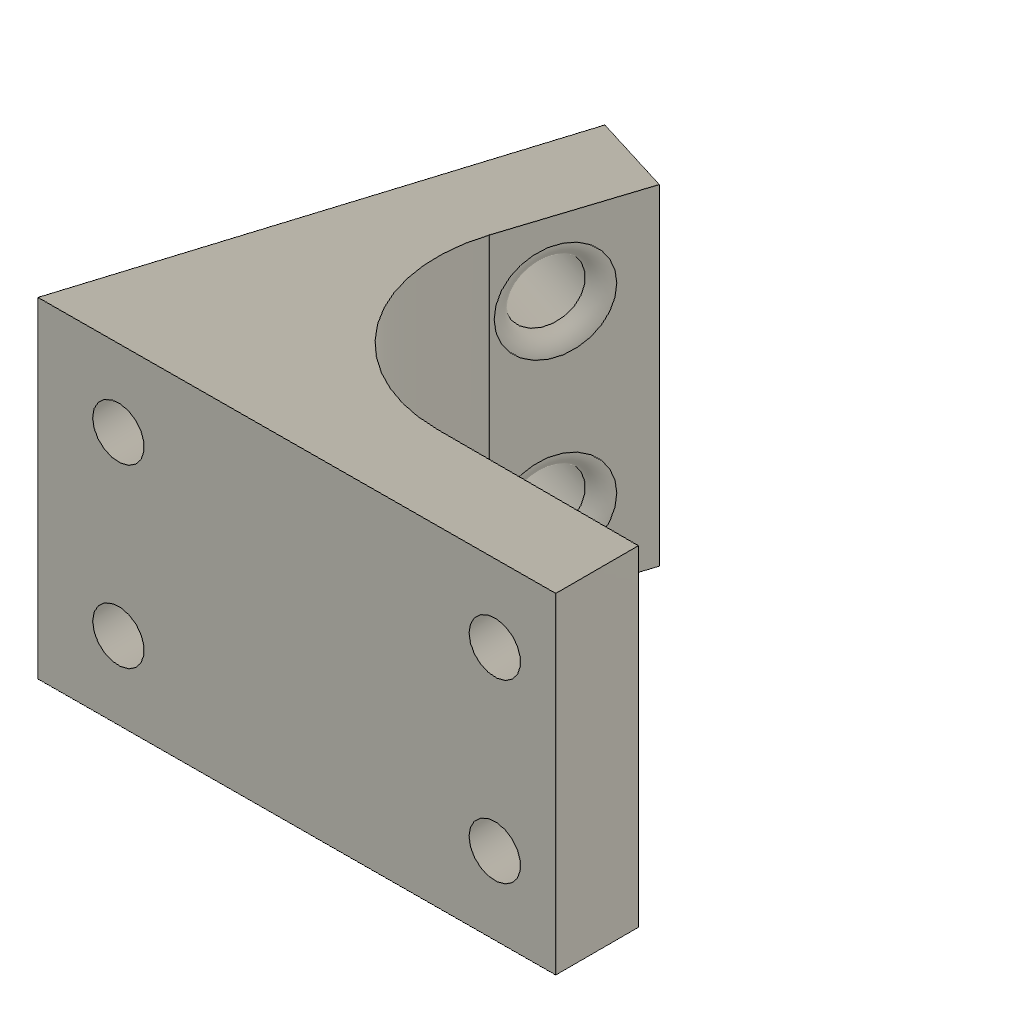
soporte_final_de_carrera_izquierdo (Autodesk Fusion 360 design; units mm, degrees)
Autodesk Fusion 360 part; units mm, degrees
sketch "Boceto1" plane through (0, 0, 0) normal (0, 1, 0) x (1, 0, 0)
sketch "Boceto2" plane through (0, 0, 0) normal (0, 1, 0) x (1, 0, 0)
  line L0 (-2.4765, -16.3875) -> (28.7043, -16.2321)
  line L1 (-0.8695, -11.2008) -> (-2.4765, -16.3875)
  line L2 (28.7038, -11.2321) -> (-0.8695, -11.2008)
  line L3 (28.7043, -16.2321) -> (28.7038, -11.2321)
  line L4 (0.003, -0.5995) -> (0.0504, -0.0236)
  line L5 (5.8748, 9.7875) -> (5.6392, 9.8069)
  line L6 (-2.0966, -0.0236) -> (7.9894, -0.0236) construction
  line L7 (-0.8695, -11.2008) -> (0.0412, -8.2614)
  line L8 (0.0412, -8.2614) -> (3.4344, 2.6907)
  line L9 (3.4344, 2.6907) -> (5.6392, 9.8069)
  line L10 (5.6392, 9.8069) -> (10.4153, 8.3271)
  line L11 (10.4153, 8.3271) -> (4.1469, -11.2061)
  line L12 (5.8705, 9.7352) -> (5.8748, 9.7875)
  line L13 (0, 0) -> (0.003, -0.5995) construction
  line L14 (0.0412, -8.2614) -> (0.0922, -18.4956) construction
  point P0 (3.4743, -16.237)
  point P1 (-1.1967, -15.176)
  point P2 (-1.5762, -19.7876)
  dimension "d1" = 5
  dimension "d3" = 5.1866
  dimension "d4" = 17.5
  dimension "d27" = 3.0772
  dimension "d28" = 5
  constraint coincident L11.end L2
  constraint coincident L13.start origin
  constraint perpendicular L0 L14
  constraint perpendicular L4 L5
  constraint parallel L1 L7
  constraint parallel L7 L8
  constraint parallel L8 L9
  constraint perpendicular L9 L10
  constraint coincident L10 L12.start
  constraint collinear L13 L14
  measures "d1" distance of L2.start L0.end
  measures "d3" vertical distance of L1.start L0.start
  measures "d4" angle of L1 L14
  measures "d27" distance of L1.start L7.end
  measures "d28" distance of L5.end L10.end
extrude "Extruir1" add sketch "Boceto2" along normal blind 20 contours L0 L1 L2 L3 | L2 L7 L8 L9 L10 L11
sketch "Boceto4" plane through (0.0816, 0, 16.3747) normal (0.004984, 0, 0.999988) x (0.999988, 0, -0.004984)
  line L0 (-2.5581, 0) -> (28.6231, 0)
  line L1 (28.6231, 0) -> (28.6231, 20)
  line L2 (28.6231, 20) -> (-2.5581, 20)
  line L3 (-2.5581, 20) -> (-2.5581, 0)
  line L4 (-0.378, 2.01) -> (27.622, 2.01)
  line L5 (27.622, 2.01) -> (27.622, 18.01)
  line L6 (27.622, 18.01) -> (-0.378, 18.01)
  line L7 (-0.378, 18.01) -> (-0.378, 2.01)
  line L8 (-0.378, 2.01) -> (27.622, 18.01) construction
  line L9 (27.622, 2.01) -> (-0.378, 18.01) construction
  circle A0 centre (2.292, 15.34) radius 1.55
  line L10 (13.622, 8.2976) -> (13.622, 12.2565) construction
  line L11 (11.7827, 10.01) -> (15.7906, 10.01) construction
  circle A1 centre (24.952, 15.34) radius 1.55
  circle A2 centre (24.952, 4.68) radius 1.55
  circle A3 centre (2.292, 4.68) radius 1.55
  point P0 (13.622, 10.01)
  dimension "d17" = 28
  dimension "d18" = 16
  dimension "d19" = 3.1
  dimension "d20" = 2.67
  dimension "d21" = 2.67
  constraint horizontal L4
  constraint perpendicular L4 L5
  constraint parallel L4 L6
  constraint parallel L5 L7
  constraint coincident L8 P0
  constraint coincident L9 P0
  constraint perpendicular L2 L10
  constraint perpendicular L10 L11
  constraint symmetric A0 L10 A1
  constraint symmetric A0 L11 A3
  constraint symmetric L11 A1 A2
  measures "d17" distance of L5.end L6.end
  measures "d18" distance of L4.end L5.end
  measures "d19" diameter of A0
  measures "d20" distance of L6 A0.centre
  measures "d21" distance of L7 A0.centre
extrude "Extruir3" cut sketch "Boceto4" against normal blind 6 contours A0 | A1 | A2 | A3
sketch "Boceto5" plane through (7.0201, 0, 2.2528) normal (0.952174, 0, 0.305557) x (0.305557, 0, -0.952174)
  line L0 (-9.4031, 0) -> (11.1113, 0)
  line L1 (11.1113, 0) -> (11.1113, 20)
  line L2 (11.1113, 20) -> (-9.4031, 20)
  line L3 (-9.4031, 20) -> (-9.4031, 0)
  circle A0 centre (6.1113, 4.5) radius 1.95
  circle A1 centre (6.1113, 15.5) radius 1.95
  dimension "d29" = 3.9
  dimension "d30" = 4.5
  dimension "d31" = 3.9
  dimension "d32" = 4.5
  dimension "d33" = 5
  dimension "d34" = 5
  measures "d29" diameter of A0
  measures "d30" distance of L0 A0.centre
  measures "d31" diameter of A1
  measures "d32" distance of L2 A1.centre
  measures "d33" distance of L1 A0.centre
  measures "d34" distance of L1 A1.centre
extrude "Extruir4" cut sketch "Boceto5" against normal blind 7 contours A0 | A1
fillet "Empalme3" radius 1 2 edges at (8.332, 5.2052, -1.8352) (8.332, 16.2052, -1.8352)
fillet "Empalme4" radius 9 1 edges at (4.1469, 10, 11.2061)
equation "d20 = 1.12 mm + ( 3.1 / 2 ) * 1 mm"
equation "d21 = 1.12 mm + ( 3.1 / 2 ) * 1 mm"
